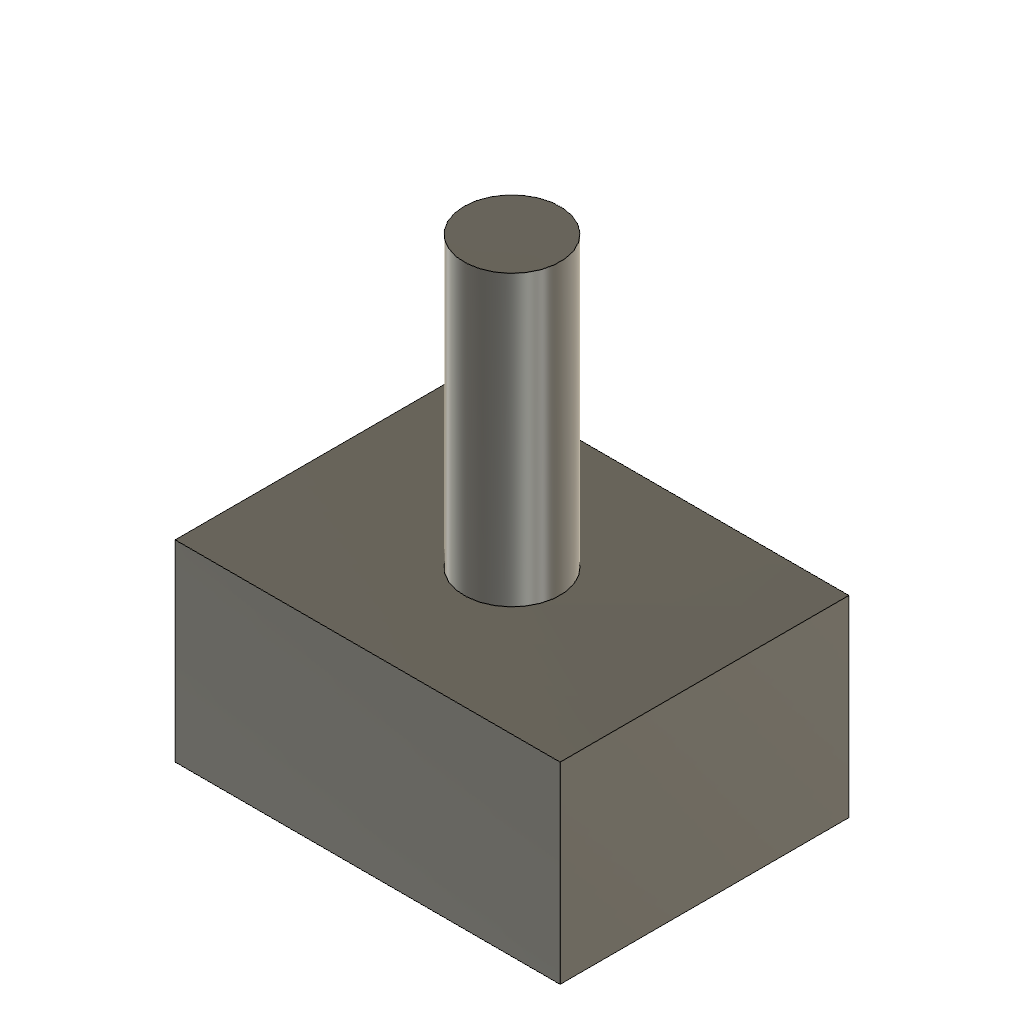
ExtrudeToObject (Autodesk Fusion 360 design; units mm, degrees)
part number: 2026-11-12-11-46-32-939
Autodesk Fusion 360 part; units mm, degrees
sketch "Base sketch" plane through (0, 0, 0) normal (0, 0, 1) x (1, 0, 0)
  line L0 (0, 0) -> (40, 0)
  line L1 (40, 0) -> (40, 30)
  line L2 (40, 30) -> (0, 30)
  line L3 (0, 30) -> (0, 0)
extrude "Base extrude" add sketch "Base sketch" along normal blind 20
ref_plane "WorkPlane1" through (0, 0, 50) normal (0, 0, 1) x (1, 0, 0)
sketch "Drop sketch" plane through (0, 0, 50) normal (0, 0, 1) x (1, 0, 0)
  circle A0 centre (20, 15) radius 5
extrude "Drop extrude" add sketch "Drop sketch" against normal up to surface (30 mm away)
